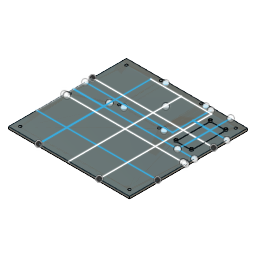
Bottom panel (Autodesk Fusion 360 design; units mm, degrees)
Autodesk Fusion 360 part; units mm, degrees
sketch "Sketch1" plane through (0, 0, 0) normal (0, 0, 1) x (1, 0, 0)
  line L0 (0, 0) -> (205, 0)
  line L1 (205, 0) -> (205, 190)
  line L2 (205, 190) -> (0, 190)
  line L3 (0, 190) -> (0, 0)
  dimension "d1" = 205
  dimension "d2" = 190
  constraint horizontal L0
  constraint vertical L1
  constraint horizontal L2
  constraint vertical L3
  constraint coincident L0.start L3.end
  measures "d1" distance of L0.start L0.end
  measures "d2" distance of L0.start L2.end
extrude "Extrude1" add sketch "Sketch1" along normal blind 4
sketch "Sketch2" plane through (0, 0, 4) normal (0, 0, 1) x (-1, 0, 0)
  line L0 (0, -190) -> (0, 0)
  line L1 (0, 0) -> (-205, 0)
  line L2 (-205, 0) -> (-205, -190)
  line L3 (-205, -190) -> (0, -190)
  line L4 (-102.5, 0) -> (-102.5, -190)
  line L5 (0, -95) -> (-205, -95)
  line L6 (-102.5, -190) -> (-153.75, -190)
  line L7 (-102.5, -190) -> (-51.25, -190)
  line L8 (-51.25, -190) -> (-51.25, 0)
  line L9 (-153.75, -190) -> (-153.75, 0)
  line L10 (0, -95) -> (0, -142.5)
  line L11 (0, -95) -> (0, -47.5)
  line L12 (0, -142.5) -> (-205, -142.5)
  line L13 (0, -47.5) -> (-205, -47.5)
  dimension "d5" = 51.25
  dimension "d6" = 47.5
  constraint midpoint L1 L4.start
  constraint midpoint L3 L4.end
  constraint midpoint L0 L5.start
  constraint midpoint L2 L5.end
  constraint perpendicular L2 L6
  constraint horizontal L7
  constraint coincident L1 L8.end
  constraint perpendicular L1 L8
  constraint coincident L1 L9.end
  constraint perpendicular L1 L9
  constraint coincident L0 L10.end
  constraint perpendicular L5 L11
  constraint coincident L2 L12.end
  constraint perpendicular L2 L12
  constraint coincident L2 L13.end
  constraint perpendicular L2 L13
  measures "d5" distance of L4.end L6.end
  measures "d6" distance of L5.start L10.end
sketch "Sketch3" plane through (0, 0, 4) normal (0, 0, 1) x (-1, 0, 0)
  line L0 (0, -95) -> (-4, -95)
  line L1 (-205, -95) -> (-201, -95)
  dimension "d7" = 4
  dimension "d8" = 4
  constraint horizontal L0
  constraint horizontal L1
  measures "d7" distance of L0.start L0.end
  measures "d8" distance of L1.start L1.end
sketch "Sketch4" plane through (0, 0, 4) normal (0, 0, 1) x (-1, 0, 0)
  circle A0 centre (-4, -95) radius 2.1
  circle A1 centre (-201, -95) radius 2.1
  dimension "d9" = 4.2
  dimension "d10" = 4.2
  measures "d9" diameter of A0
  measures "d10" diameter of A1
extrude "Extrude2" cut sketch "Sketch4" against normal blind 4
sketch "Sketch5" plane through (0, 0, 4) normal (0, 0, 1) x (-1, 0, 0)
  line L0 (-51.25, 0) -> (-51.25, -110)
  line L1 (-51.25, -110) -> (0, -110)
  line L2 (0, -110) -> (-205, -110)
  line L3 (-51.25, -110) -> (-51.25, -120)
  line L4 (0, -130) -> (-60, -130)
  line L5 (-60, -130) -> (-148, -130)
  line L6 (-148, -130) -> (-148, -195)
  point P0 (-104, -162.5)
  dimension "d13" = 110
  dimension "d14" = 10
  dimension "d15" = 60
  dimension "d16" = 88
  constraint vertical L0
  constraint perpendicular L0 L1
  constraint perpendicular L0 L2
  constraint perpendicular L2 L3
  constraint perpendicular L3 L4
  constraint horizontal L5
  constraint vertical L6
  measures "d13" distance of L0.start L0.end
  measures "d14" distance of L0.end L3.end
  measures "d15" distance of L4.start L4.end
  measures "d16" distance of L4.end L5.end
sketch "Sketch6" plane through (0, 0, 4) normal (0, 0, 1) x (-1, 0, 0)
  line L0 (-138, -125.5) -> (-70, -125.5)
  line L1 (-70, -125.5) -> (-70, -196.5)
  line L2 (-70, -196.5) -> (-138, -196.5)
  line L3 (-138, -196.5) -> (-138, -125.5)
  line L4 (-138, -125.5) -> (-70, -196.5) construction
  line L5 (-70, -125.5) -> (-138, -196.5) construction
  circle A0 centre (-70, -196.5) radius 1.7
  circle A1 centre (-138, -196.5) radius 1.7
  circle A2 centre (-70, -125.5) radius 1.7
  circle A3 centre (-138, -125.5) radius 1.7
  point P0 (-104, -161)
  dimension "d21" = 68
  dimension "d22" = 71
  dimension "d23" = 3.4
  dimension "d24" = 3.4
  dimension "d25" = 3.4
  dimension "d26" = 3.4
  constraint horizontal L0
  constraint perpendicular L0 L1
  constraint parallel L0 L2
  constraint parallel L1 L3
  constraint coincident L4 P0
  constraint coincident L5 P0
  constraint coincident L1.end L2.start
  constraint coincident L2.end L3.start
  constraint coincident L0.end L1.start
  constraint coincident L0.start L3.end
  measures "d21" distance of L1.end L2.end
  measures "d22" distance of L0.end L1.end
  measures "d23" diameter of A0
  measures "d24" diameter of A1
  measures "d25" diameter of A2
  measures "d26" diameter of A3
extrude "Extrude3" add 1 faces at (136.6667, 190, 1.3333) along direction (0, 1, 0) blind 10
extrude "Extrude4" cut sketch "Sketch6" against normal blind 4 contours L0 L3 A3 | L0 L3 A3 | L0 L1 A2 | L0 L1 A2 | L2 L3 A1 | L2 L3 A1 | L1 L2 A0 | L1 L2 A0
sketch "Sketch7" plane through (0, 0, 4) normal (0, 0, 1) x (-1, 0, 0)
  line L0 (-205, -165) -> (-148, -165)
  line L1 (-148, -165) -> (-176.5, -165)
  line L2 (-176.5, -200) -> (-176.5, -110)
  constraint horizontal L0
  constraint midpoint L0 L1.end
  constraint perpendicular L1 L2
sketch "Sketch8" plane through (0, 0, 4) normal (0, 0, 1) x (-1, 0, 0)
  line L0 (0, -200) -> (0, 0)
  line L1 (0, 0) -> (-205, 0)
  line L2 (-205, 0) -> (-205, -200)
  line L3 (-205, -200) -> (0, -200)
  circle A0 centre (-201, -95) radius 2.1
  circle A1 centre (-4, -95) radius 2.1
  circle A2 centre (-70, -125.5) radius 1.7
  circle A3 centre (-70, -196.5) radius 1.7
  circle A4 centre (-138, -125.5) radius 1.7
  circle A5 centre (-138, -196.5) radius 1.7
  line L4 (-163.35, -120.4) -> (-189.65, -120.4)
  line L5 (-189.65, -120.4) -> (-189.65, -178.6)
  line L6 (-189.65, -178.6) -> (-163.35, -178.6)
  line L7 (-163.35, -178.6) -> (-163.35, -120.4)
  line L8 (-163.35, -120.4) -> (-189.65, -178.6) construction
  line L9 (-189.65, -120.4) -> (-163.35, -178.6) construction
  point P0 (-176.5, -149.5)
  dimension "d31" = 26.3
  dimension "d32" = 58.2
  constraint horizontal L4
  constraint perpendicular L4 L5
  constraint parallel L4 L6
  constraint parallel L5 L7
  constraint coincident L8 P0
  constraint coincident L9 P0
  measures "d31" distance of L5.end L6.end
  measures "d32" distance of L4.end L5.end
sketch "Sketch9" plane through (0, 0, 4) normal (0, 0, 1) x (-1, 0, 0)
  circle A0 centre (-163.35, -178.6) radius 1.7
  circle A1 centre (-189.65, -178.6) radius 1.7
  circle A2 centre (-189.65, -120.4) radius 1.7
  circle A3 centre (-163.35, -120.4) radius 1.7
  dimension "d33" = 3.4
  dimension "d34" = 3.4
  dimension "d35" = 3.4
  dimension "d36" = 3.4
  measures "d33" diameter of A0
  measures "d34" diameter of A1
  measures "d35" diameter of A2
  measures "d36" diameter of A3
extrude "Extrude5" cut sketch "Sketch9" against normal blind 4
sketch "Sketch10" plane through (0, 0, 4) normal (0, 0, 1) x (-1, 0, 0)
  circle A0 centre (-163.35, -120.4) radius 2.5
  circle A1 centre (-189.65, -120.4) radius 2.5
  circle A2 centre (-189.65, -178.6) radius 2.5
  circle A3 centre (-163.35, -178.6) radius 2.5
  circle A4 centre (-163.35, -178.6) radius 1.7
  circle A5 centre (-189.65, -178.6) radius 1.7
  circle A6 centre (-163.35, -120.4) radius 1.7
  circle A7 centre (-189.65, -120.4) radius 1.7
  dimension "d39" = 5
  dimension "d40" = 5
  dimension "d41" = 5
  dimension "d42" = 5
  dimension "d43" = 3.4
  dimension "d44" = 3.4
  dimension "d45" = 3.4
  dimension "d46" = 3.4
  constraint concentric A3 A4
  constraint concentric A2 A5
  constraint concentric A0 A6
  constraint concentric A1 A7
  measures "d39" diameter of A0
  measures "d40" diameter of A1
  measures "d41" diameter of A2
  measures "d42" diameter of A3
  measures "d43" diameter of A4
  measures "d44" diameter of A5
  measures "d45" diameter of A6
  measures "d46" diameter of A7
extrude "Extrude6" add sketch "Sketch10" along normal blind 2.6
extrude "Extrude7" cut 4 faces at (190.3469, 180.7157, 6.6) (161.1882, 179.1369, 6.6) (164.0469, 122.5157, 6.6) (190.3469, 122.5157, 6.6) along direction (0, 0, -1) blind 0.6
extrude "Extrude8" cut sketch "Sketch8" against normal blind 0.6 contours L4 L5 L6 L7
sketch "Sketch11" plane through (0, 0, 4) normal (0, 0, 1) x (-1, 0, 0)
  circle A0 centre (-4, -95) radius 2.1
  circle A1 centre (-201, -95) radius 2.1
  dimension "d53" = 4.2
  dimension "d54" = 4.2
  measures "d53" diameter of A0
  measures "d54" diameter of A1
extrude "Extrude9" add sketch "Sketch11" against normal blind 4
sketch "Sketch12" plane through (0, 0, 0) normal (0, 0, -1) x (1, 0, 0)
  circle A0 centre (138, -196.5) radius 1.7
  circle A1 centre (138, -125.5) radius 1.7
  circle A2 centre (70, -196.5) radius 1.7
  circle A3 centre (70, -125.5) radius 1.7
  line L0 (0, 0) -> (0, -200)
  line L1 (0, -200) -> (205, -200)
  line L2 (205, -200) -> (205, 0)
  line L3 (205, 0) -> (0, 0)
  circle A4 centre (189.65, -120.4) radius 1.7
  circle A5 centre (163.35, -178.6) radius 1.7
  circle A6 centre (163.35, -120.4) radius 1.7
  circle A7 centre (189.65, -178.6) radius 1.7
  line L4 (205, -100) -> (0, -100)
  line L5 (205, -100) -> (201, -100)
  line L6 (0, -100) -> (4, -100)
  circle A8 centre (4, -100) radius 2.1
  circle A9 centre (201, -100) radius 2.1
  dimension "d57" = 4
  dimension "d58" = 4
  dimension "d59" = 4.2
  dimension "d60" = 4.2
  constraint midpoint L2 L4.start
  constraint midpoint L0 L4.end
  constraint perpendicular L2 L5
  constraint perpendicular L0 L6
  constraint coincident L6.end A8.centre
  constraint coincident L5.end A9.centre
  measures "d57" distance of L4.start L5.end
  measures "d58" distance of L4.end L6.end
  measures "d59" diameter of A8
  measures "d60" diameter of A9
extrude "Extrude10" cut sketch "Sketch12" against normal blind 4 contours L4 L6 A8 | L4 L6 A8 | L4 L5 A9 | L4 L5 A9
sketch "Sketch13" plane through (0, 0, 0) normal (0, 0, -1) x (1, 0, 0)
  circle A0 centre (189.65, -178.6) radius 1.7
  circle A1 centre (163.35, -120.4) radius 1.7
  circle A2 centre (163.35, -178.6) radius 1.7
  circle A3 centre (189.65, -120.4) radius 1.7
  line L0 (0, 0) -> (0, -200)
  line L1 (0, -200) -> (205, -200)
  line L2 (205, -200) -> (205, 0)
  line L3 (205, 0) -> (0, 0)
  circle A4 centre (70, -125.5) radius 1.7
  circle A5 centre (70, -196.5) radius 1.7
  circle A6 centre (138, -125.5) radius 1.7
  circle A7 centre (138, -196.5) radius 1.7
  circle A8 centre (4, -100) radius 2.1
  circle A9 centre (201, -100) radius 2.1
  circle A10 centre (138, -196.5) radius 2.1
  circle A11 centre (138, -125.5) radius 2.1
  circle A12 centre (70, -125.5) radius 2.1
  circle A13 centre (70, -196.5) radius 2.1
  dimension "d63" = 4.2
  dimension "d64" = 4.2
  dimension "d65" = 4.2
  dimension "d66" = 4.2
  constraint concentric A7 A10
  constraint concentric A6 A11
  constraint concentric A4 A12
  constraint concentric A5 A13
  measures "d63" diameter of A10
  measures "d64" diameter of A11
  measures "d65" diameter of A12
  measures "d66" diameter of A13
extrude "Extrude11" cut sketch "Sketch13" against normal blind 4 contours A10 | A11 | A12 | A13
sketch "Sketch14" plane through (0, 0, 4) normal (0, 0, 1) x (-1, 0, 0)
  circle A0 centre (-201, -100) radius 2.1
  circle A1 centre (-4, -100) radius 2.1
  line L0 (-189.65, -176.1) -> (-189.65, -122.9)
  arc A2 (-187.15, -120.4) -> (-189.65, -122.9) centre (-189.65, -120.4) ccw
  line L1 (-187.15, -120.4) -> (-165.85, -120.4)
  arc A3 (-163.35, -122.9) -> (-165.85, -120.4) centre (-163.35, -120.4) ccw
  line L2 (-163.35, -122.9) -> (-163.35, -176.1)
  arc A4 (-165.85, -178.6) -> (-163.35, -176.1) centre (-163.35, -178.6) ccw
  line L3 (-165.85, -178.6) -> (-187.15, -178.6)
  arc A5 (-189.65, -176.1) -> (-187.15, -178.6) centre (-189.65, -178.6) ccw
  line L4 (0, -200) -> (0, 0)
  line L5 (0, 0) -> (-205, 0)
  line L6 (-205, 0) -> (-205, -200)
  line L7 (-205, -200) -> (0, -200)
  circle A6 centre (-138, -125.5) radius 2.1
  circle A7 centre (-138, -196.5) radius 2.1
  circle A8 centre (-70, -125.5) radius 2.1
  circle A9 centre (-70, -196.5) radius 2.1
  circle A10 centre (-70, -196.5) radius 2.1
  circle A11 centre (-138, -196.5) radius 2.1
  circle A12 centre (-138, -125.5) radius 2.1
  circle A13 centre (-70, -125.5) radius 2.1
  constraint concentric A9 A10
  constraint concentric A7 A11
  constraint concentric A6 A12
  constraint concentric A8 A13
sketch "Sketch15" plane through (0, 0, 0) normal (0, 0, -1) x (1, 0, 0)
  circle A0 centre (201, -100) radius 2.1
  circle A1 centre (4, -100) radius 2.1
  line L0 (0, 0) -> (0, -200)
  line L1 (0, -200) -> (205, -200)
  line L2 (205, -200) -> (205, 0)
  line L3 (205, 0) -> (0, 0)
  circle A2 centre (189.65, -120.4) radius 1.7
  circle A3 centre (163.35, -178.6) radius 1.7
  circle A4 centre (163.35, -120.4) radius 1.7
  circle A5 centre (189.65, -178.6) radius 1.7
  circle A6 centre (138, -125.5) radius 2.1
  circle A7 centre (138, -196.5) radius 2.1
  circle A8 centre (70, -125.5) radius 2.1
  circle A9 centre (70, -196.5) radius 2.1
  circle A10 centre (70, -125.5) radius 2.1
  circle A11 centre (138, -125.5) radius 2.1
  circle A12 centre (138, -196.5) radius 2.1
  circle A13 centre (70, -196.5) radius 2.1
  constraint concentric A8 A10
  constraint concentric A6 A11
  constraint concentric A7 A12
  constraint concentric A9 A13
extrude "Extrude12" add sketch "Sketch15" against normal blind 4 contours A6 A11 | A7 A12 | A8 A10 | A9 A13
sketch "Sketch16" plane through (0, 0, 4) normal (0, 0, 1) x (-1, 0, 0)
  circle A0 centre (-130, -125.5) radius 2.1
  circle A1 centre (-62, -125.5) radius 2.1
  circle A2 centre (-62, -196.5) radius 2.1
  circle A3 centre (-130, -196.5) radius 2.1
  dimension "d71" = 4.2
  dimension "d72" = 4.2
  dimension "d73" = 4.2
  dimension "d74" = 4.2
  measures "d71" diameter of A0
  measures "d72" diameter of A1
  measures "d73" diameter of A2
  measures "d74" diameter of A3
extrude "Extrude13" cut sketch "Sketch16" against normal blind 7654
sketch "Sketch17" plane through (0, 0, 0) normal (0, 0, -1) x (1, 0, 0)
  circle A0 centre (189.65, -178.6) radius 1.7
  circle A1 centre (163.35, -120.4) radius 1.7
  circle A2 centre (163.35, -178.6) radius 1.7
  circle A3 centre (189.65, -120.4) radius 1.7
  line L0 (0, 0) -> (0, -200)
  line L1 (0, -200) -> (205, -200)
  line L2 (205, -200) -> (205, 0)
  line L3 (205, 0) -> (0, 0)
  circle A4 centre (4, -100) radius 2.1
  circle A5 centre (201, -100) radius 2.1
  circle A6 centre (130, -196.5) radius 2.1
  circle A7 centre (130, -125.5) radius 2.1
  circle A8 centre (62, -196.5) radius 2.1
  circle A9 centre (62, -125.5) radius 2.1
  line L4 (10, -10) -> (195, -10)
  line L5 (195, -10) -> (195, -190)
  line L6 (195, -190) -> (10, -190)
  line L7 (10, -190) -> (10, -10)
  line L8 (10, -10) -> (195, -190) construction
  line L9 (195, -10) -> (10, -190) construction
  circle A10 centre (195, -190) radius 2.1
  circle A11 centre (10, -190) radius 2.1
  circle A12 centre (195, -10) radius 2.1
  circle A13 centre (10, -10) radius 2.1
  point P0 (102.5, -100)
  dimension "d77" = 4.2
  dimension "d78" = 4.2
  dimension "d79" = 4.2
  dimension "d80" = 4.2
  constraint horizontal L4
  constraint perpendicular L4 L5
  constraint parallel L4 L6
  constraint parallel L5 L7
  constraint coincident L8 P0
  constraint coincident L9 P0
  constraint coincident L5.end L6.start
  constraint coincident L6.end L7.start
  constraint coincident L4.end L5.start
  constraint coincident L4.start L7.end
  measures "d77" diameter of A10
  measures "d78" diameter of A11
  measures "d79" diameter of A12
  measures "d80" diameter of A13
extrude "Extrude14" cut sketch "Sketch17" against normal blind 4 contours L4 L7 A13 | L4 L7 A13 | L4 L5 A12 | L4 L5 A12 | L6 L7 A11 | L6 L7 A11 | L5 L6 A10 | L5 L6 A10
equation "d5 = ( 102.500 / 2 ) * 1 mm"
equation "d6 = ( 95 / 2 ) * 1 mm"
equation "d7 = 1.9 mm + 2.1 mm"
